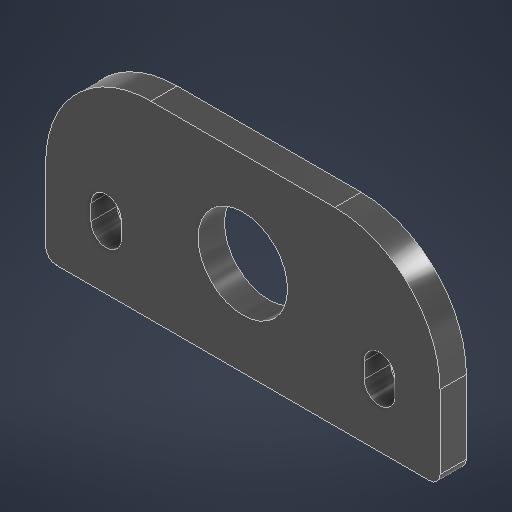
# Autodesk Inventor part: Cylinder Bracket
Saved by Autodesk Inventor 2027.1 (Build 311270010, 270A)
## iProperties
Created: 2026-11-17
Part Number: Cylinder Bracket
Material: Wood (Oak)
Document SubType Name: Modeling
Designer: Ahmed
Density: 0.76 g/cm^3
Appearance: Dark Gray
Author: Ahmed
Autodesk Inventor part; units mm, degrees
ref_plane "YZ Plane" through (0, 0, 0) normal (1, 0, 0) x (0, 1, 0)
ref_plane "XZ Plane" through (0, 0, 0) normal (0, 1, 0) x (-1, 0, 0)
ref_plane "XY Plane" through (0, 0, 0) normal (0, 0, 1) x (1, 0, 0)
sketch "Sketch1" plane through (0, 0, 0) normal (0, 0, 1) x (1, 0, 0)
  line L0 (-17.5, 18) -> (17.5, 18)
  line L1 (37.5, -2) -> (37.5, -16)
  line L2 (35.5, -18) -> (-35.5, -18)
  line L3 (-37.5, -16) -> (-37.5, -2)
  line L4 (-37.5, 18) -> (37.5, -18) construction
  line L5 (37.5, 18) -> (-37.5, -18) construction
  circle A0 centre (0, 0) radius 8.5
  arc A1 (-17.5, 18) -> (-37.5, -2) centre (-17.5, -2) ccw
  arc A2 (37.5, -2) -> (17.5, 18) centre (17.5, -2) ccw
  arc A3 (-37.5, -16) -> (-35.5, -18) centre (-35.5, -16) ccw
  arc A4 (35.5, -18) -> (37.5, -16) centre (35.5, -16) ccw
  line L6 (-26, -7.5) -> (-26, -4.5) construction
  line L7 (-28.9, -7.5) -> (-28.9, -4.5)
  line L8 (-23.1, -4.5) -> (-23.1, -7.5)
  arc A5 (-28.9, -7.5) -> (-23.1, -7.5) centre (-26, -7.5) ccw
  arc A6 (-23.1, -4.5) -> (-28.9, -4.5) centre (-26, -4.5) ccw
  line L9 (0, -18) -> (0, 18) construction
  line L10 (26, -7.5) -> (26, -4.5) construction
  line L11 (28.9, -7.5) -> (28.9, -4.5)
  line L12 (23.1, -4.5) -> (23.1, -7.5)
  arc A7 (23.1, -7.5) -> (28.9, -7.5) centre (26, -7.5) ccw
  arc A8 (28.9, -4.5) -> (23.1, -4.5) centre (26, -4.5) ccw
  point P0 (-26, -6)
  point P1 (26, -6)
  dimension "d0" = 75
  dimension "d1" = 36
  dimension "d2" = 17
  dimension "d3" = 20
  dimension "d4" = 2
  dimension "d7" = 3
  dimension "d8" = 2.9
  dimension "d9" = 10.5
  dimension "d11" = 26
  constraints: 30 end point, 16 point on circle, 12 tangent, 9 centre point, 8 point on line, 7 symmetric about line, 5 midpoint, 3 parallel, 2 equal radius, 1 coincident, 1 horizontal, 1 perpendicular, 1 vertical, 2 other
  measures "d0" distance of L4.end L5.end
  measures "d1" distance of L5.start L4.end
  measures "d2" diameter of A0
  measures "d3" radius of A1
  measures "d4" radius of A3
  measures "d7" distance of L6.start L6.end
  measures "d8" radius of A5
  measures "d9" distance from line of L2 L6.start
  measures "d11" horizontal distance of point (0, 0) point (-26, -6)
extrude "Extrusion1" add sketch "Sketch1" along normal blind 5
body "Solid1"
